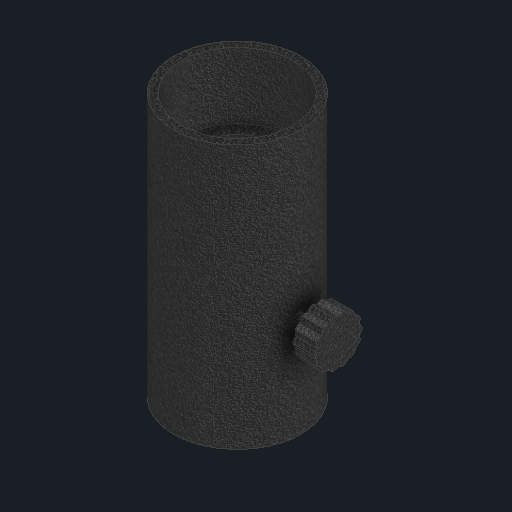
# Autodesk Inventor part: tripod_leg_clamp
Saved by Autodesk Inventor 2027.1 (Build 311270010, 270A)
## iProperties
Created: 2026-11-04
Part Number: tripod_leg_clamp
Material: Generic
Description: Leg extension clamp with knob
Document SubType Name: Modeling
Designer: Claude (from photos)
Density: 1 g/cm^3
Appearance: Black Cast
Author: alexg
Autodesk Inventor part; units mm, degrees
ref_plane "Work Plane1" through (0, -570, 0) normal (0, 1, 0) x (-1, 0, 0)
sketch "Clamp sleeve on upper leg sketch" plane through (0, -570, 0) normal (0, 1, 0) x (-1, 0, 0)
  circle A0 centre (0, 0) radius 29
  circle A1 centre (0, 0) radius 25.4
  constraints: 2 centre point
extrude "Clamp sleeve on upper leg" add sketch "Clamp sleeve on upper leg sketch" against normal blind 30
ref_plane "Work Plane2" through (0, -600, 0) normal (0, 1, 0) x (-1, 0, 0)
sketch "Clamp body sketch" plane through (0, -600, 0) normal (0, 1, 0) x (-1, 0, 0)
  circle A0 centre (0, 0) radius 29
  circle A1 centre (0, 0) radius 19.2
  constraints: 2 centre point
extrude "Clamp body" add sketch "Clamp body sketch" against normal blind 90
ref_plane "Work Plane3" through (28, 0, 0) normal (1, 0, 0) x (0, 1, 0)
sketch "Clamp screw sketch" plane through (28, 0, 0) normal (1, 0, 0) x (0, 1, 0)
  circle A0 centre (-645, 0) radius 4
  constraints: 1 centre point
extrude "Clamp screw" add sketch "Clamp screw sketch" along normal blind 9
ref_plane "Work Plane4" through (36, 0, 0) normal (1, 0, 0) x (0, 1, 0)
sketch "Clamp knob sketch" plane through (36, 0, 0) normal (1, 0, 0) x (0, 1, 0)
  line L0 (-645, 11) -> (-642.7748, 9.7493)
  line L1 (-642.7748, 9.7493) -> (-640.2273, 9.9107)
  line L2 (-640.2273, 9.9107) -> (-638.7651, 7.8183)
  line L3 (-638.7651, 7.8183) -> (-636.3999, 6.8584)
  line L4 (-636.3999, 6.8584) -> (-635.9903, 4.3388)
  line L5 (-635.9903, 4.3388) -> (-634.2758, 2.4477)
  line L6 (-634.2758, 2.4477) -> (-635, 0)
  line L7 (-635, 0) -> (-634.2758, -2.4477)
  line L8 (-634.2758, -2.4477) -> (-635.9903, -4.3388)
  line L9 (-635.9903, -4.3388) -> (-636.3999, -6.8584)
  line L10 (-636.3999, -6.8584) -> (-638.7651, -7.8183)
  line L11 (-638.7651, -7.8183) -> (-640.2273, -9.9107)
  line L12 (-640.2273, -9.9107) -> (-642.7748, -9.7493)
  line L13 (-642.7748, -9.7493) -> (-645, -11)
  line L14 (-645, -11) -> (-647.2252, -9.7493)
  line L15 (-647.2252, -9.7493) -> (-649.7727, -9.9107)
  line L16 (-649.7727, -9.9107) -> (-651.2349, -7.8183)
  line L17 (-651.2349, -7.8183) -> (-653.6001, -6.8584)
  line L18 (-653.6001, -6.8584) -> (-654.0097, -4.3388)
  line L19 (-654.0097, -4.3388) -> (-655.7242, -2.4477)
  line L20 (-655.7242, -2.4477) -> (-655, 0)
  line L21 (-655, 0) -> (-655.7242, 2.4477)
  line L22 (-655.7242, 2.4477) -> (-654.0097, 4.3388)
  line L23 (-654.0097, 4.3388) -> (-653.6001, 6.8584)
  line L24 (-653.6001, 6.8584) -> (-651.2349, 7.8183)
  line L25 (-651.2349, 7.8183) -> (-649.7727, 9.9107)
  line L26 (-649.7727, 9.9107) -> (-647.2252, 9.7493)
  line L27 (-647.2252, 9.7493) -> (-645, 11)
  constraints: 56 end point
extrude "Clamp knob" add sketch "Clamp knob sketch" along normal blind 10
body "Solid1"
